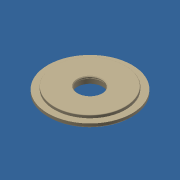
# Autodesk Inventor part: 15-0012-0322
Saved by Autodesk Inventor 2016 SP1 (Build 200210100, 210)
## iProperties
Created: 2017-10-18
Part Number: 15-0012-0322
Material: Plastic (PEEK)
Document SubType Name: Modeling
Designer: Hans Ellermeijer
Density: 1.32 g/cm^3
Appearance: Beige
Project: Quantum Gas Microscope
Cost Center: 15-0012
User Status: Work in Progress
Authority: Georgios Siviloglou
RuleStatus: InUse
Category: IOP
Company: Universiteit van Amsterdam
BeforeDocSave0: Open Form
Author: Hans Ellermeijer
Title: Quantum Gas Microscope
Revision Number: A
Autodesk Inventor part; units mm, degrees
ref_plane "YZ Plane" through (0, 0, 0) normal (1, 0, 0) x (0, 1, 0)
ref_plane "XZ Plane" through (0, 0, 0) normal (0, 1, 0) x (-1, 0, 0)
ref_plane "XY Plane" through (0, 0, 0) normal (0, 0, 1) x (1, 0, 0)
sketch "Sketch1" plane through (0, 0, 0) normal (0, 0, 1) x (1, 0, 0)
  line L0 (0, 49) -> (0, -49) construction
  line L1 (-49, 0) -> (49, 0) construction
  circle A0 centre (0, 0) radius 35
  circle A1 centre (0, 0) radius 25.4
  dimension "d0" = 70
  dimension "d3" = 50.8
  constraints: 2 centre point, 2 coincident
  measures "d0" diameter of A0
  measures "d3" diameter of A1
sketch "Sketch2" plane through (0, 0, 0) normal (0, 1, 0) x (-1, 0, 0)
  line L0 (30, 6.69) -> (30, 4.69)
  line L1 (30, 4.69) -> (29, 3.69)
  line L2 (29, 3.69) -> (9, 3.69)
  line L3 (9, 3.69) -> (9, 7.19)
  line L4 (9, 7.19) -> (8.5, 7.19)
  line L5 (25.4, 8.69) -> (25.4, 6.69)
  line L6 (0, -31.24) -> (0, 16.64) projected
  line L7 (8.5, 7.19) -> (8.5, 7.69)
  line L8 (8.5, 7.69) -> (8.5, 7.69)
  line L9 (25.4, 8.69) -> (8.5, 8.69)
  line L10 (8.5, 8.69) -> (8.5, 7.69)
  line L11 (30, 6.69) -> (25.4, 6.69)
  line L12 (-49, 0) -> (49, 0) construction
  circle A0 centre (0, -7.3) radius 17.1 construction
  line L13 (8.5, 7.5406) -> (9, 7.2429)
  line L14 (8.75, 7.3917) -> (0, -7.3) construction
  line L15 (9, 7.2429) -> (9.0768, 7.1971)
  arc A1 (9.1289, 6.9915) -> (9.0768, 7.1971) centre (9, 7.0683) ccw
  line L16 (9.1289, 6.9915) -> (9, 6.7751)
  point P0 (0, 0)
  dimension "d4" = 18
  dimension "d5" = 60
  dimension "d6" = 50.8
  dimension "d7" = 3.5
  dimension "d8" = 17
  dimension "d9" = 0.5
  dimension "d10" = 58
  dimension "d15" = 45
  dimension "d16" = 1
  dimension "d17" = 17
  dimension "d28" = 34.2
  dimension "d29" = 15.99
  dimension "d42" = 0.15
  dimension "d43" = 0
  dimension "d45" = 3.69
  dimension "d46" = 2
  constraints: 30 end point, 8 perpendicular, 3 point on line, 3 tangent, 2 centre point, 2 midpoint, 2 point on circle, 2 vertical, 1 collinear, 1 horizontal, 1 parallel
  measures "d4" diameter of L3 L6
  measures "d5" diameter of L0 L6
  measures "d6" diameter of L5 L6
  measures "d7" distance of L2.end L3.end
  measures "d8" diameter of L7 L6
  measures "d9" distance of L4.end L7.end
  measures "d10" diameter of L1.end L6
  measures "d15" angle of L1 L0
  measures "d16" distance of L9.end L8.end
  measures "d17" diameter of L10 L6
  measures "d28" diameter of A0
  measures "d29" distance from line of L14.end L9
  measures "d42" radius of A1
  measures "d43" distance from line of L3 A1.centre
  measures "d45" distance between parallel lines of L12 L2
  measures "d46" distance of L5.start L5.end
revolve "Revolution1" add sketch "Sketch2" angle 360 about axis through (0, 0, 0) along (0, 0, 1)
fillet "Fillet1" radius 0.4 1 edges at (25.4, 0, 8.69)
chamfer "Chamfer1" distance 0.5 angle 45 1 edges at (8.5, 0, 8.69)
revolve "Revolution3" cut sketch "Sketch2" angle 360 about axis through (0, 0, 0) along (0, 0, 1) contours L3 L4 L7 L13 L15 A1 L16
body "Solid2"
